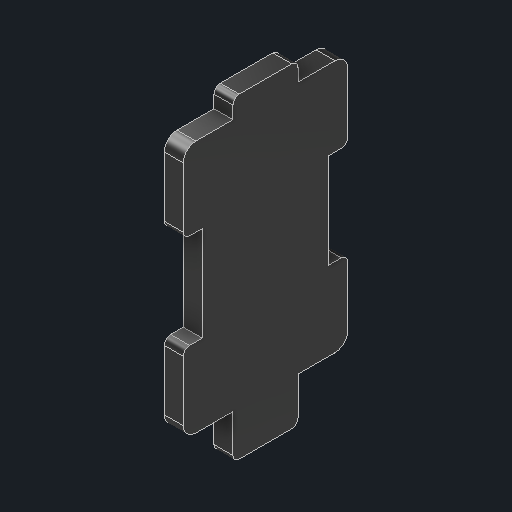
# Autodesk Inventor part: RxSide
Saved by Autodesk Inventor 2027.1 (Build 311270010, 270A)
## iProperties
Created: 2026-10-19
Part Number: RxSide
Material: MDF Medium Density Fiberboard
Document SubType Name: Modeling
Designer: SDS Scholar
Density: 0.8 g/cm^3
Appearance: Glossy - Black
Mass: 2.51484 g
Surface Area: 25.671 cm^2
Volume: 3.14355 cm^3
Author: SDS Scholar
Autodesk Inventor part; units mm, degrees
ref_plane "YZ Plane" through (0, 0, 0) normal (1, 0, 0) x (0, 1, 0)
ref_plane "XZ Plane" through (0, 0, 0) normal (0, 1, 0) x (-1, 0, 0)
ref_plane "XY Plane" through (0, 0, 0) normal (0, 0, 1) x (1, 0, 0)
sketch "Sketch2" plane through (0, 0, 0) normal (1, 0, 0) x (0, 1, 0)
  line L0 (20, 13) -> (-20, 13)
  line L1 (-20, 13) -> (-20, -13)
  line L2 (-20, -13) -> (20, -13)
  line L3 (20, -13) -> (20, 13)
  line L4 (-20, 5.15) -> (-27, 5.15)
  line L5 (-27, 5.15) -> (-27, -5.15)
  line L6 (-27, -5.15) -> (-20, -5.15)
  line L7 (-20, -5.15) -> (-20, 5.15)
  line L8 (7.5, -13) -> (-7.5, -13)
  line L9 (-7.5, -13) -> (-7.5, -10)
  line L10 (-7.5, -10) -> (7.5, -10)
  line L11 (7.5, -10) -> (7.5, -13)
  line L12 (20, 0) -> (-20, 0) construction
  line L13 (20, 5.15) -> (23, 5.15)
  line L14 (23, 5.15) -> (23, -5.15)
  line L15 (23, -5.15) -> (20, -5.15)
  line L16 (20, -5.15) -> (20, 5.15)
  line L17 (-7.5, 13) -> (-7.5, 10)
  line L18 (-7.5, 10) -> (7.5, 10)
  line L19 (7.5, 10) -> (7.5, 13)
  point P0 (0, 0)
  point P1 (0, -13)
  point P2 (-27, 0)
  point P3 (0, -10)
  point P4 (20, 5.15)
  point P5 (-20, -5.15)
  point P6 (20, -5.15)
  dimension "d0" = 26
  dimension "d1" = 40
  dimension "d2" = 7
  dimension "d3" = 10.3
  dimension "d4" = 15
  dimension "d5" = 3
  dimension "d6" = 3
  dimension "d7" = 10.3
  constraints: 40 end point, 8 parallel, 6 midpoint, 4 horizontal, 4 perpendicular, 4 symmetric about line, 2 horizontal alignment, 2 point on line, 2 vertical alignment
  measures "d0" distance of L0.end L1.end
  measures "d1" distance of L1.end L2.end
  measures "d2" distance of L5.end L6.end
  measures "d3" distance of L4.end L5.end
  measures "d4" distance of L9.end L10.end
  measures "d5" distance of L10.end L8.start
  measures "d6" distance of L13.start L13.end
  measures "d7" distance of L13.end L14.end
extrude "Extrusion1" add sketch "Sketch2" along normal blind 3 contours L3 L2 L11 L10 L9 L1 L0 L17 L18 L19 | L13 L14 L15 L3 | L1 L6 L5 L4
fillet "Fillet1" radius 2 4 edges at (1.5, 20, 13) (1.5, 20, -13) (1.5, -20, 13) (1.5, -20, -13)
fillet "Fillet2" radius 1 8 edges at (1.5, 23, 5.15) (1.5, 23, -5.15) (1.5, 7.5, -13) (1.5, -7.5, -13) (1.5, -27, -5.15) (1.5, -27, 5.15) (1.5, -7.5, 13) (1.5, 7.5, 13)
equation "\"d1\" = ProductBaseHeight"
equation "\"d2\" = BaseWoodThickness"
equation "\"ProductBaseHeight\" = 40"
equation "\"GridProcutClearance\" = 5"
equation "\"GridBorderThickness\" = 5"
equation "\"GridBorderFillets\" = 7"
equation "\"GridTotalSize\" = 65"
equation "\"GridRobotClearance\" = 65"
equation "\"AluminiumExtrusionClearance\" = 35"
equation "\"BaseTotalLength\" = 885"
equation "\"WorkspaceLength\" = 515"
equation "\"WorkspaceHeight\" = 183"
equation "\"AxesBaseFillet\" = 15"
equation "\"Zaxis\" = 197"
equation "\"ProductTotalHeight\" = 45"
equation "\"VerticalStroke\" = 105"
equation "\"BackArea\" = 165"
equation "\"CylinderStroke\" = 75"
equation "\"BoxesWidth\" = 125"
equation "\"BaseWoodThickness\" = 7"
equation "\"Kerf\" = 0.3"
equation "\"RxThickness\" = 1.8"
equation "\"support_2\" = 265"
body "Solid1"
